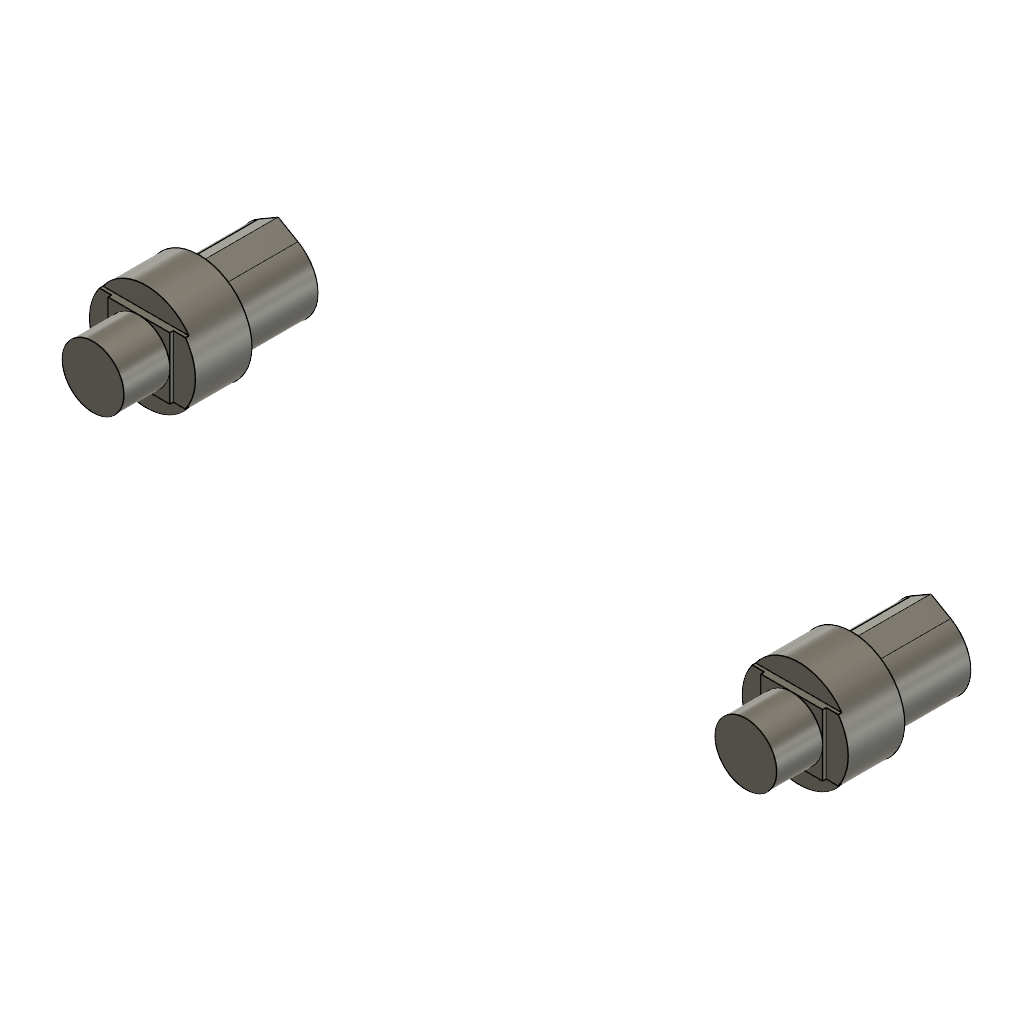
replica_screwholes (Autodesk Fusion 360 design; units mm, degrees)
part number: 2026-11-10-15-27-37-058
Autodesk Fusion 360 part; units mm, degrees
ref_plane "WorkPlane1" through (0, 0, 23.05) normal (0, 0, 1) x (1, 0, 0)
sketch "body" plane through (0, 0, 23.05) normal (0, 0, 1) x (1, 0, 0)
  line L0 (-17.8431, 20) -> (-27.5, 10.3431)
  arc A0 (-27.5, 6.3199) -> (-26.3302, 3.1059) centre (-22.5, 6.3199) ccw
  line L1 (-26.3302, 3.1059) -> (-20.5096, -3.8308)
  arc A1 (-20.5096, -3.8308) -> (-20.2023, -4.1741) centre (-15, 0.7923) ccw
  spline S0 degree 3 poles (-15, -12.3777) (-15, -11.8756) (-15.1011, -11.391) (-15.518, -10.2882) (-15.8904, -9.6934) (-16.8948, -8.3522) (-17.5903, -7.5923) (-18.9478, -5.9881) (-19.6232, -5.1384) (-20.2023, -4.1741) knots 0 0 0 0 0.150622 0.150622 0.352713 0.352713 0.618566 0.618566 0.862231 0.862231 0.862231 0.862231
  line L2 (-15, -12.3777) -> (-15, -15)
  line L3 (-15, -15) -> (15, -15)
  line L4 (15, -15) -> (15, -12.3777)
  spline S1 degree 3 poles (20.2023, -4.1741) (19.4898, -5.3606) (18.6277, -6.379) (17.0639, -8.1888) (16.3407, -9.0062) (15.5692, -10.2511) (15.3569, -10.6701) (15.075, -11.5247) (15, -11.9454) (15, -12.3777) knots 0 0 0 0 0.415181 0.415181 0.816478 0.816478 1.004003 1.004003 1.177971 1.177971 1.177971 1.177971
  arc A2 (20.2023, -4.1741) -> (20.5096, -3.8308) centre (15, 0.7923) ccw
  line L5 (20.5096, -3.8308) -> (26.3302, 3.1059)
  arc A3 (26.3302, 3.1059) -> (27.5, 6.3199) centre (22.5, 6.3199) ccw
  line L6 (27.5, 10.3431) -> (17.8431, 20)
  line L7 (17.8431, 20) -> (-17.8431, 20)
  circle A4 centre (17.5, 4.3) radius 1.75
  circle A5 centre (17.5, 4.3) radius 2.25
  circle A6 centre (17.5, 4.3) radius 3
  circle A7 centre (-19.5, 4.3) radius 1.75
  circle A8 centre (-19.5, 4.3) radius 2.25
  circle A9 centre (-19.5, 4.3) radius 3
  line L8 (16.375, 6.2486) -> (17.5, 6.8981)
  line L9 (17.5, 6.8981) -> (18.625, 6.2486)
  line L10 (-20.625, 6.2486) -> (-19.5, 6.8981)
  line L11 (-19.5, 6.8981) -> (-18.375, 6.2486)
  line L12 (-5.7276, 13.4917) -> (-4.2276, 12.6256)
  arc A10 (-7.2276, 12.6256) -> (-4.2276, 12.6256) centre (-5.7276, 10.0276) ccw
  line L13 (-7.2276, 12.6256) -> (-5.7276, 13.4917)
  line L14 (-5.7276, 2.0365) -> (-4.2276, 1.1705)
  arc A11 (-7.2276, 1.1705) -> (-4.2276, 1.1705) centre (-5.7276, -1.4276) ccw
  line L15 (-7.2276, 1.1705) -> (-5.7276, 2.0365)
  line L16 (5.7276, 13.4917) -> (7.2276, 12.6256)
  arc A12 (4.2276, 12.6256) -> (7.2276, 12.6256) centre (5.7276, 10.0276) ccw
  line L17 (4.2276, 12.6256) -> (5.7276, 13.4917)
  arc A13 (4.2276, 1.1705) -> (7.2276, 1.1705) centre (5.7276, -1.4276) ccw
  line L18 (4.2276, 1.1705) -> (5.7276, 2.0365)
  line L19 (5.7276, 2.0365) -> (7.2276, 1.1705)
  line L20 (0, 6.7826) -> (1.075, 6.162)
  arc A14 (-1.075, 6.162) -> (1.075, 6.162) centre (0, 4.3) ccw
  line L21 (-1.075, 6.162) -> (0, 6.7826)
  line L22 (-27.5, 10.3431) -> (-27.5, 6.3199)
  line L23 (27.5, 6.3199) -> (27.5, 10.3431)
extrude "Extrusion1" add sketch "body" against normal blind 4.5 contours A4 | A5 | A5 L8 L9 | A7 | A8 | A8 L10 L11 makes body 1 at (16.2793, 6.1901, 21.55) makes body 2 at (-18.7834, 2.1672, 20.05)
extrude "Extrusion2" add sketch "body" along normal blind 3 contours A4 | A5 | A5 L8 L9 | A6 | A7 | A8 | A8 L10 L11 | A9 bodies 1 2
extrude "Extrusion3" add sketch "body" along normal blind 3 from surface at 3 contours A4 | A7 bodies 1 2
ref_plane "WorkPlane2" through (0, 0, 26.05) normal (0, 0, 1) x (1, 0, 0)
sketch "screwhole_bridge" plane through (0, 0, 26.05) normal (0, 0, 1) x (1, 0, 0)
  circle A0 centre (17.5, 4.3) radius 1.75
  circle A1 centre (17.5, 4.3) radius 3
  circle A2 centre (-19.5, 4.3) radius 1.75
  circle A3 centre (-19.5, 4.3) radius 3
  line L0 (15.0633, 6.05) -> (19.9367, 6.05)
  line L1 (15.0633, 2.55) -> (19.9367, 2.55)
  line L2 (15.75, 6.05) -> (15.75, 2.55)
  line L3 (19.25, 6.05) -> (19.25, 2.55)
  line L4 (-21.9367, 6.05) -> (-17.0633, 6.05)
  line L5 (-21.9367, 2.55) -> (-17.0633, 2.55)
  line L6 (-17.75, 6.05) -> (-17.75, 2.55)
  line L7 (-21.25, 6.05) -> (-21.25, 2.55)
extrude "Extrusion4" add sketch "screwhole_bridge" along normal blind 0.2 contours A1 L0 L1 L3 | A1 L0 L1 L2 | A3 L4 L5 L6 | A3 L4 L5 L7 bodies 1 2
extrude "Extrusion5" add sketch "screwhole_bridge" along normal blind 0.4 contours A0 L1 L3 | A0 L0 L3 | A0 L0 L2 | A0 L1 L2 | A2 L5 L6 | A2 L4 L6 | A2 L4 L7 | A2 L5 L7 bodies 1 2
equation "hotend_length = 54 mm" comment "Lenght of the uhf hotend for the uhf cowls. Default: 54mm  (Pheatus dragon UHF alike)"
equation "hotend_screwhole_radius = 8.1 mm" comment "Radius of the mounting screholes. Default: 8,10mm (pheatus dragon alike)"
equation "hotend_diameter = 22.2 mm" comment "Diameter of the kotend heatsink. Default: 22,20mm (pheatus dragon alike)"
equation "DS_adapter_lenght = 35.75 mm" comment "Lenght or depth of the DraftShift adapter. Default: 35,75m"
equation "extruder_screwholes_right = 17.5 mm" comment "Right extruder screwhole, distance from center. Orbiter:  17,5 Sherpa_mini:  21,75 Sherpa_micro:  18.05"
equation "extruder_screwholes_left = 19.5 mm" comment "Left extruder screwhole, distance from center. Orbiter:  16,5 Sherpa_mini:  21,75 Sherpa_micro:  13,95"
equation "heat_insert_diameter = 4.5 mm" comment "Diameter of the M3 heated inserts holes, Default: 4.5mm"
